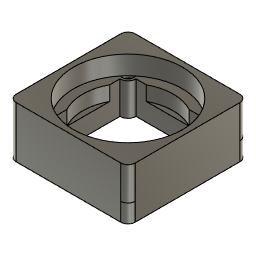
C mount v1 (Autodesk Fusion 360 design; units mm, degrees)
Autodesk Fusion 360 part; units mm, degrees
note: some values were not read from the file. Set by a fixed rule: which sketch regions a step uses; the direction of a hole.
sketch "Sketch1" plane through (0, 0, 0) normal (0, 0, 1) x (1, 0, 0)
  line L0 (2, 0) -> (31, 0)
  line L1 (33, 2) -> (33, 31)
  line L2 (31, 33) -> (2, 33)
  line L3 (0, 31) -> (0, 2)
  line L4 (30, 3) -> (3, 3)
  line L5 (3, 3) -> (3, 30)
  line L6 (3, 30) -> (30, 30)
  line L7 (30, 30) -> (30, 3)
  line L8 (30, 3) -> (3, 30) construction
  line L9 (3, 3) -> (30, 30) construction
  line L10 (5.5, 3) -> (5.5, 5.5)
  line L11 (5.5, 5.5) -> (27.5, 5.5)
  circle A0 centre (5.5, 5.5) radius 1
  circle A1 centre (27.5, 5.5) radius 1
  line L12 (5.5, 5.5) -> (5.5, 27.5)
  circle A2 centre (5.5, 27.5) radius 1
  line L13 (5.5, 27.5) -> (27.5, 27.5)
  circle A3 centre (27.5, 27.5) radius 1
  circle A4 centre (5.5, 27.5) radius 2.25
  circle A5 centre (27.5, 27.5) radius 2.25
  circle A6 centre (5.5, 5.5) radius 2.25
  circle A7 centre (27.5, 5.5) radius 2.25
  line L14 (27.5, 27.5) -> (27.5, 5.5)
  arc A8 (2, 33) -> (0, 31) centre (2, 31) ccw
  arc A9 (33, 31) -> (31, 33) centre (31, 31) ccw
  arc A10 (0, 2) -> (2, 0) centre (2, 2) ccw
  arc A11 (31, 0) -> (33, 2) centre (31, 2) ccw
  point P0 (33, 0)
  point P1 (0, 33)
  point P2 (16.5, 16.5)
  dimension "d1" = 33
  dimension "d2" = 33
  dimension "d4" = 27
  dimension "d5" = 27
  dimension "d7" = 2.5
  dimension "d10" = 2
  dimension "d11" = 2
  dimension "d12" = 22
  dimension "d13" = 2
  dimension "d14" = 2
  dimension "d15" = 4.5
  dimension "d16" = 4.5
  dimension "d17" = 4.5
  dimension "d18" = 4.5
  dimension "d21" = 2
  dimension "d22" = 2
  dimension "d23" = 2
  dimension "d24" = 2
  constraint horizontal L0
  constraint vertical L1
  constraint horizontal L2
  constraint vertical L3
  constraint horizontal L4
  constraint perpendicular L4 L5
  constraint parallel L4 L6
  constraint parallel L5 L7
  constraint coincident L8 P2
  constraint coincident L9 P2
  constraint coincident L4 L10.start
  constraint coincident L10.end L11.start
  constraint coincident L11.end A1.centre
  constraint vertical L12
  constraint perpendicular L11 L12
  constraint coincident L12.end A2.centre
  constraint coincident L9 L13.end
  constraint horizontal L13
  constraint coincident L13.end A3.centre
  constraint concentric A2 A4
  constraint concentric A3 A5
  constraint concentric A0 A6
  constraint concentric A1 A7
  constraint perpendicular L11 L14
  constraint coincident P1 L3
  constraint coincident P1 L2
  constraint tangent L3 A8
  constraint tangent L2 A8
  constraint tangent L2 A9
  constraint tangent L1 A9
  constraint coincident origin L0
  constraint coincident origin L3
  constraint tangent L0 A10
  constraint tangent L3 A10
  constraint coincident P0 L0
  constraint coincident P0 L1
  constraint tangent L0 A11
  constraint tangent L1 A11
  measures "d1" distance of origin P0
  measures "d2" distance of origin P1
  measures "d4" distance of L5.end L6.end
  measures "d5" distance of L4.end L5.end
  measures "d7" distance of L10.start L10.end
  measures "d10" diameter of A0
  measures "d11" diameter of A1
  measures "d12" distance of L10.end L12.end
  measures "d13" diameter of A2
  measures "d14" diameter of A3
  measures "d15" diameter of A4
  measures "d16" diameter of A5
  measures "d17" diameter of A6
  measures "d18" diameter of A7
  measures "d21" radius of A8
  measures "d22" radius of A9
  measures "d23" radius of A10
  measures "d24" radius of A11
extrude "Extrude1" add sketch "Sketch1" along normal blind 5 contours L0 L1 L2 L3 A8 A9 A10 A11 | L10 A0 L12 A6 | L10 L11 A0 A6 | L4 L5 L6 L7 | L11 A0 L12 A6 | L12 A2 L13 A4 | L12 A2 L13 A4 | L11 A1 A7 L14 | L11 A1 A7 L14 | L13 A3 A5 L14 | L13 A3 A5 L14
sketch "Sketch4" plane through (0, 0, 5) normal (0, 0, 1) x (-1, 0, 0)
  circle A0 centre (-5.5, -27.5) radius 1
  circle A1 centre (-27.5, -27.5) radius 1
  circle A2 centre (-27.5, -5.5) radius 1
  line L0 (-25.25, -5.5) -> (-7.75, -5.5)
  arc A3 (-7.75, -5.5) -> (-5.5, -7.75) centre (-5.5, -5.5) ccw
  line L1 (-5.5, -7.75) -> (-5.5, -25.25)
  arc A4 (-5.5, -25.25) -> (-7.75, -27.5) centre (-5.5, -27.5) ccw
  line L2 (-7.75, -27.5) -> (-25.25, -27.5)
  arc A5 (-25.25, -27.5) -> (-27.5, -25.25) centre (-27.5, -27.5) ccw
  line L3 (-27.5, -25.25) -> (-27.5, -7.75)
  arc A6 (-27.5, -7.75) -> (-25.25, -5.5) centre (-27.5, -5.5) ccw
  circle A7 centre (-5.5, -5.5) radius 1
  arc A8 (-31, 0) -> (-33, -2) centre (-31, -2) ccw
  line L4 (-33, -2) -> (-33, -31)
  arc A9 (-33, -31) -> (-31, -33) centre (-31, -31) ccw
  line L5 (-31, -33) -> (-2, -33)
  arc A10 (-2, -33) -> (0, -31) centre (-2, -31) ccw
  line L6 (0, -31) -> (0, -2)
  arc A11 (0, -2) -> (-2, 0) centre (-2, -2) ccw
  line L7 (-2, 0) -> (-31, 0)
  line L8 (-2, 0) -> (-31, 0)
  line L9 (-33, -2) -> (-33, -31)
  line L10 (-31, -33) -> (-2, -33)
  line L11 (0, -31) -> (0, -2)
  arc A12 (-2, -33) -> (0, -31) centre (-2, -31) ccw
  arc A13 (0, -2) -> (-2, 0) centre (-2, -2) ccw
  arc A14 (-33, -31) -> (-31, -33) centre (-31, -31) ccw
  arc A15 (-31, 0) -> (-33, -2) centre (-31, -2) ccw
  circle A16 centre (-16.5, -16.5) radius 12.5
  dimension "d25" = 2
  dimension "d26" = 2
  dimension "d27" = 2
  dimension "d28" = 2
  dimension "d29" = 25
  constraint horizontal L8
  constraint vertical L9
  constraint horizontal L10
  constraint vertical L11
  constraint tangent L10 A12
  constraint tangent L11 A12
  constraint tangent L8 A13
  constraint tangent L11 A13
  constraint tangent L9 A14
  constraint tangent L10 A14
  constraint tangent L8 A15
  constraint tangent L9 A15
  measures "d25" radius of A12
  measures "d26" radius of A13
  measures "d27" radius of A14
  measures "d28" radius of A15
  measures "d29" diameter of A16
extrude "Extrude2" add sketch "Sketch4" along normal blind 4
sketch "Sketch5" plane through (0, 0, 9) normal (0, 0, 1) x (-1, 0, 0)
  line L0 (-5.5, -22.4372) -> (-5.5, -25.25)
  arc A0 (-5.5, -25.25) -> (-7.75, -27.5) centre (-5.5, -27.5) ccw
  line L1 (-7.75, -27.5) -> (-10.5628, -27.5)
  arc A1 (-22.4372, -27.5) -> (-10.5628, -27.5) centre (-16.5, -16.5) ccw
  line L2 (-22.4372, -27.5) -> (-25.25, -27.5)
  arc A2 (-25.25, -27.5) -> (-27.5, -25.25) centre (-27.5, -27.5) ccw
  line L3 (-27.5, -25.25) -> (-27.5, -22.4372)
  arc A3 (-27.5, -10.5628) -> (-27.5, -22.4372) centre (-16.5, -16.5) ccw
  line L4 (-27.5, -10.5628) -> (-27.5, -7.75)
  arc A4 (-27.5, -7.75) -> (-25.25, -5.5) centre (-27.5, -5.5) ccw
  line L5 (-25.25, -5.5) -> (-22.4372, -5.5)
  arc A5 (-10.5628, -5.5) -> (-22.4372, -5.5) centre (-16.5, -16.5) ccw
  line L6 (-10.5628, -5.5) -> (-7.75, -5.5)
  arc A6 (-7.75, -5.5) -> (-5.5, -7.75) centre (-5.5, -5.5) ccw
  line L7 (-5.5, -7.75) -> (-5.5, -10.5628)
  arc A7 (-5.5, -22.4372) -> (-5.5, -10.5628) centre (-16.5, -16.5) ccw
  circle A8 centre (-5.5, -5.5) radius 1
  circle A9 centre (-27.5, -5.5) radius 1
  circle A10 centre (-27.5, -27.5) radius 1
  circle A11 centre (-5.5, -27.5) radius 1
  arc A12 (-31, 0) -> (-33, -2) centre (-31, -2) ccw
  line L8 (-33, -2) -> (-33, -31)
  arc A13 (-33, -31) -> (-31, -33) centre (-31, -31) ccw
  line L9 (-31, -33) -> (-2, -33)
  arc A14 (-2, -33) -> (0, -31) centre (-2, -31) ccw
  line L10 (0, -31) -> (0, -2)
  arc A15 (0, -2) -> (-2, 0) centre (-2, -2) ccw
  line L11 (-2, 0) -> (-31, 0)
  circle A16 centre (-16.5, -16.5) radius 15.05
  dimension "d32" = 30.1
  constraint concentric A1 A16
  measures "d32" diameter of A16
extrude "Extrude3" add sketch "Sketch5" along normal blind 5.2 contours A8 A16 | A9 A16 | A11 A16 | A10 A16 | A12 L8 A13 L9 A14 L10 A15 L11 picked at (-5.4913, -5.518) picked at (-27.0159, -5.9669) picked at (-5.9756, -27.0244) picked at (-27.5124, -27.4778)
hole "Hole1" at (5.5, 27.5, 9) direction (0, 0, -1) diameter 3.2 depth 2 tip angle 118
hole "Hole2" at (27.5, 27.5, 9) direction (0, 0, 1) diameter 3.2 depth 2 tip angle 118
hole "Hole3" at (5.5, 5.5, 9) direction (0, 0, 1) diameter 3.2 depth 2 tip angle 118
hole "Hole4" at (27.5, 5.5, 9) direction (0, 0, -1) diameter 3.2 depth 2 tip angle 118
